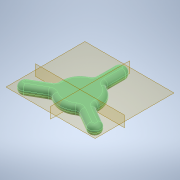
# Autodesk Inventor part: Whippletree
Saved by Autodesk Inventor 2021 (Build 250183000, 183)
## iProperties
Created: 2026-04-22
Part Number: Whippletree
Material: Generic
Document SubType Name: Modeling
Designer: Admin
Density: 1 g/cm^3
Appearance: Smooth - Dark Forest Green
Author: Admin
Autodesk Inventor part; units mm, degrees
sketch "Sketch1" plane through (0, 0, 0) normal (0, 1, 0) x (-1, 0, 0)
  line L0 (0, 0) -> (0, -20) construction
  line L1 (-3, 0) -> (-3, -20)
  line L2 (3, -20) -> (3, 0)
  arc A0 (3, 0) -> (-3, 0) centre (0, 0) ccw
  arc A1 (-3, -20) -> (3, -20) centre (0, -20) ccw
  line L3 (0, 0) -> (17.3205, 10) construction
  line L4 (1.5, -2.5981) -> (18.8205, 7.4019)
  line L5 (15.8205, 12.5981) -> (-1.5, 2.5981)
  arc A2 (-1.5, 2.5981) -> (1.5, -2.5981) centre (0, 0) ccw
  arc A3 (18.8205, 7.4019) -> (15.8205, 12.5981) centre (17.3205, 10) ccw
  line L6 (0, 0) -> (-17.3205, 10) construction
  line L7 (1.5, 2.5981) -> (-15.8205, 12.5981)
  line L8 (-18.8205, 7.4019) -> (-1.5, -2.5981)
  arc A4 (-1.5, -2.5981) -> (1.5, 2.5981) centre (0, 0) ccw
  arc A5 (-15.8205, 12.5981) -> (-18.8205, 7.4019) centre (-17.3205, 10) ccw
  circle A6 centre (0, 0) radius 10
  point P0 (0, -10)
  point P1 (8.6603, 5)
  point P2 (-8.6603, 5)
  point P3 (6.7614, 7.3678)
  point P4 (-6.7614, 7.3678)
  point P5 (-9.7614, 2.1716)
  point P6 (-3, -9.5394)
  point P7 (3, -9.5394)
  point P8 (9.7614, 2.1716)
  dimension "d0" = 3
  dimension "d1" = 20
  dimension "d4" = 360
  dimension "d6" = 20
  constraints: 24 end point, 12 point on circle, 7 centre point, 4 tangent, 3 coincident, 1 midpoint, 1 parallel, 1 vertical, 35 other
  measures "d0" radius of A1
  measures "d1" distance of L1.start L1.end
  measures "d6" diameter of A6
extrude "Extrusion1" add sketch "Sketch1" along normal mid plane 5
fillet "Fillet1" radius 2 6 edges at (-3, 0, -9.5394) (-9.7614, 0, 2.1716) (-6.7614, 0, 7.3678) (3, 0, -9.5394) (9.7614, 0, 2.1716) (6.7614, 0, 7.3678)
fillet "Fillet2" radius 2 36 edges at (-6.8534, 2.5, 7.7867) (0, 2.5, 10) (6.8534, 2.5, 7.7867) (11.8839, 2.5, 10.3253) (19.9186, 2.5, 11.5) (14.8839, 2.5, 5.1291) (10.1702, 2.5, 2.0419) (8.6603, 2.5, -5) (3.3167, 2.5, -9.8286) (3, 2.5, -15.4544) (0, 2.5, -23) (-3, 2.5, -15.4544) (-3.3167, 2.5, -9.8286) (-8.6603, 2.5, -5) (-10.1702, 2.5, 2.0419) (-14.8839, 2.5, 5.1291) (-19.9186, 2.5, 11.5) (-11.8839, 2.5, 10.3253) (-19.9186, -2.5, 11.5) (-14.8839, -2.5, 5.1291) (-10.1702, -2.5, 2.0419) (-8.6603, -2.5, -5) (-3.3167, -2.5, -9.8286) (-3, -2.5, -15.4544) (0, -2.5, -23) (3, -2.5, -15.4544) (3.3167, -2.5, -9.8286) (8.6603, -2.5, -5) (10.1702, -2.5, 2.0419) (14.8839, -2.5, 5.1291) (19.9186, -2.5, 11.5) (11.8839, -2.5, 10.3253) (6.8534, -2.5, 7.7867) (0, -2.5, 10) (-6.8534, -2.5, 7.7867) (-11.8839, -2.5, 10.3253)
body "Solid1"
